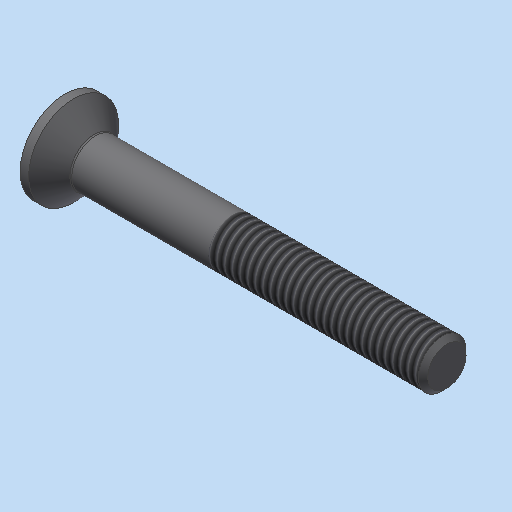
# Autodesk Inventor part: Senkschraube_ISO_10642___M5x40
Saved by Autodesk Inventor 2023.3 (Build 273359000, 359)
## iProperties
Shininess: 64.0
Length Units: 11269
Angle Units: 11279
Time Units: 11290
Mass Units: 11283
Length Display Precision: 3
Angle Display Precision: 2
Compacted: True
Part Number: Senkschraube_ISO_10642___M5x40
Document SubType Name: Modeling
Created: 2004-03-30
Material: xStahl_AnP_Dummymaterial
Description: =<RBPARTNOTITLE2>
Vendor: NORM8
Designer: S.Riedelsheimer
Manufacturer: Standard
Standards Organization: Custom
Density: 7.85 g/cm^3
Mass: 6.77567 g
Surface Area: 7.80742 cm^2
Volume: 0.863143 cm^3
Appearance: Stahl - normal AnP
Density: 0.0
Volumn: 0.0
Area: 0.0
PropertySet Name: Model Information
Control State: 0
Master: False
Checked Out: False
CNS_NB: Senkschraube ISO 10642 - M5x40
CNS_NN: ISO 10642
CNS_NT: Senkschrauben mit Innensechskant
CNS_NBSYN: Senkschraube $NENN.
CNS_LINA: Senkschraube ISO 10642 - M5x40
CNS_D: 5.000
CNS_D3: 4.019
CNS_P: 0.800
CNS_L: 40.000
CNS_S: 3.000
CNS_DK: 9.430
CNS_K: 3.100
CNS_T: 1.900
CNS_R: 0.200
CNS_LS: 14.000
CNS_LG: 18.000
CNS_NENN: ISO 10642 - M5x40
CNS_YW: 1.571
CNS_YC: 0.885
CNS_KT: DUMMY
PSOL_IDENT_0: {C:\partsolutions8\data\23d-libs\bosch_bamberg\schrauben\senkschrauben\iso_10642.prj},168 {M=Nenngew
PSOL_IDENT_1: inde},{VTYP=3D},{NB=Senkschraube ISO 10642 - M5x40},{NN=ISO 10642},{DATE=26.11.2003},{GEOMDATE=26.11
PSOL_IDENT_2: .2003},{VERSION=v1},{LINEID=250},{LINESUBID=-1},{WBVAR=}  {NB=Senkschraube ISO 10642 - M5x40},{LINA=
PSOL_IDENT_3: Senkschraube ISO 10642 - M5x40},{KT=DUMMY},{IDNR=},{D=5.000},{D3=4.019},{P=0.800},{L=40.000},{S=3.00
PSOL_IDENT_4: 0},{DK=9.430},{K=3.100},{T=1.900},{R=0.200},{LS=14.000},{LG=18.000},{NENN=ISO 10642 - M5x40},{YW=1.5
PSOL_IDENT_5: 7079},{YC=0.884987}
RBPARTNOTITLE2: Senkschrauben mit Innensechskant
RBPARTMADEOF: ISO 10642 - M5x40
RBPARTNOTITLE1: Hexagon socket countersunk head screws
RBDRAWINGMISSINGSPEC: --
AnP_Kategorie: 4
Title: Senkschraube ISO 10642 - M5x40
Author: S.Riedelsheimer
Keywords: =<RBPARTMADEOF>
Comments: =<RBSURFACE2>
Revision Number: 01
Autodesk Inventor part; units mm, degrees
sketch "Sketch_2" plane through (0, 0, 0) normal (0, 0, 1) x (1, 0, 0)
  line L0 (0.4641, 0) -> (40, 0)
  line L1 (40, 0) -> (40, -2.0095)
  line L2 (40, -2.0095) -> (39.5095, -2.5)
  line L3 (39.5095, -2.5) -> (3.1828, -2.5)
  arc A0 (3.1828, -2.5) -> (3.0414, -2.5586) centre (3.1828, -2.7) ccw
  line L4 (3.0414, -2.5586) -> (0.885, -4.715)
  line L5 (0.885, -4.715) -> (0, -4.715)
  line L6 (0, -4.715) -> (0, -1.7321)
  line L7 (0, -1.7321) -> (0.4641, 0)
  line L8 (0.4641, 0) -> (40, 0)
  constraints: 18 end point, 2 point on circle, 1 centre point
revolve "Drehung1" add sketch "Sketch_2" angle 360 about axis through (0.4641, 0, 0) along (1, 0, 0)
thread "Gewinde1" size "M5x0.8" class "6g" standard "ANSI Metric M Profile" length 22
sketch "Sketch_3" plane through (0, 0, 0) normal (1, 0, 0) x (0, 1, 0)
  line L0 (0, 1.7321) -> (-1.5, 0.866)
  line L1 (-1.5, 0.866) -> (-1.5, -0.866)
  line L2 (-1.5, -0.866) -> (0, -1.7321)
  line L3 (0, -1.7321) -> (1.5, -0.866)
  line L4 (1.5, -0.866) -> (1.5, 0.866)
  line L5 (1.5, 0.866) -> (0, 1.7321)
  constraints: 12 end point
extrude "Extrusion1" cut sketch "Sketch_3" along normal blind 1.9
ref_plane "IP1_XY" through (0, 0, 0) normal (1, 0, 0) x (0, 0, -1)
ref_plane "IP1_YZ" through (0, 0, 0) normal (0, 0, -1) x (0, 1, 0)
ref_plane "IP2_XY" through (40, 0, 0) normal (1, 0, 0) x (0, 0, -1)
ref_plane "IP2_YZ" through (40, 0, 0) normal (0, 0, -1) x (0, 1, 0)
